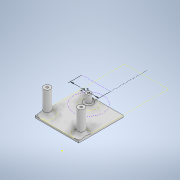
# Autodesk Inventor part: suport dintr-o bucata
Saved by Autodesk Inventor 2022.6 (Build 266554000, 554)
## iProperties
Created: 2026-10-28
Part Number: suport dintr-o bucata
Material: Generic
Document SubType Name: Modeling
Designer: Dragos Macovei
Density: 1 g/cm^3
Appearance: Default
Author: Dragos Macovei
Autodesk Inventor part; units mm, degrees
ref_plane "YZ Plane" through (0, 0, 0) normal (1, 0, 0) x (0, 1, 0)
ref_plane "XZ Plane" through (0, 0, 0) normal (0, 1, 0) x (-1, 0, 0)
ref_plane "XY Plane" through (0, 0, 0) normal (0, 0, 1) x (1, 0, 0)
sketch "Sketch1" plane through (0, 0, 0) normal (0, 1, 0) x (-1, 0, 0)
  line L0 (0, 0) -> (45, 0)
  line L1 (45, 0) -> (45, -109.7465)
  line L2 (45, -109.7465) -> (0, -109.7465)
  line L3 (0, -109.7465) -> (0, 0)
  dimension "d35" = 45
  constraints: 8 end point, 2 parallel, 1 horizontal, 1 perpendicular
  measures "d35" distance between parallel lines of L3 L1
extrude "Extrusion1" add sketch "Sketch1" along normal blind 2
sketch "Sketch2" plane through (0, 2, 0) normal (0, 1, 0) x (1, 0, 0)
  circle A0 centre (-40, 24.934) radius 3.5
  circle A1 centre (-5, 24.934) radius 3.5
  circle A2 centre (-5, 24.934) radius 1.15
  circle A3 centre (-40, 24.934) radius 1.15
  line L0 (0, 0) -> (0, 109.7465) projected
  dimension "d2" = 35
  dimension "d3" = 7
  dimension "d4" = 7
  dimension "d5" = 2.3
  dimension "d6" = 2.3
  dimension "d7" = 5
  constraints: 4 centre point, 2 coincident
  measures "d2" distance of A0.centre A1.centre
  measures "d3" diameter of A1
  measures "d4" diameter of A0
  measures "d5" diameter of A2
  measures "d6" diameter of A3
  measures "d7" distance from line of L0 A1.centre
extrude "Extrusion2" add sketch "Sketch2" along normal blind 24
sketch "Sketch3" plane through (0, 2, 0) normal (0, 1, 0) x (1, 0, 0)
  circle A0 centre (-40, 24.934) radius 1.15 projected
  circle A1 centre (-5, 24.934) radius 1.15 projected
  line L0 (-50.8787, 24.934) -> (5.8787, 24.934) construction
  line L1 (-22.5, 24.934) -> (-22.5, 31.434) construction
  circle A2 centre (-22.5, 31.434) radius 2.5 construction
  circle A3 centre (-22.5, 31.434) radius 4.5415 construction
  circle A4 centre (-27.7085, 55.203) radius 2.65
  circle A5 centre (-27.7085, 55.203) radius 1.15
  line L2 (-22.5, 24.934) -> (-22.5, 95.6611)
  circle A6 centre (-27.7085, 55.203) radius 20.2915 construction
  line L3 (-22.5, 55.203) -> (-52, 55.203)
  circle A7 centre (-52, 55.203) radius 4.5
  point P0 (0, 0)
  dimension "d10" = 6.5
  dimension "d11" = 5
  dimension "d12" = 9.083
  dimension "d15" = 5.3
  dimension "d16" = 2.3
  dimension "d31" = 17.5
  dimension "d39" = 40.583
  dimension "d40" = 29.5
  dimension "d41" = 9
  dimension "d42" = 0.5
  dimension "d43" = 0.5
  constraints: 8 end point, 6 centre point, 5 coincident, 3 point on line, 2 horizontal, 2 vertical, 1 midpoint
  measures "d10" distance of L1.start L1.end
  measures "d11" diameter of A2
  measures "d12" diameter of A3
  measures "d15" diameter of A4
  measures "d16" diameter of A5
  measures "d31" distance from line of A1.centre L1
  measures "d39" diameter of A6
  measures "d40" distance of L3.start L3.end
  measures "d41" diameter of A7
extrude "Extrusion3" add sketch "Sketch3" along normal blind 10 contours L3 A5 A4 | A4 L3 A5
sketch "Sketch4" plane through (0, 2, 0) normal (0, 1, 0) x (1, 0, 0)
  line L0 (0, 109.7465) -> (-45, 109.7465) projected
  line L1 (-45, 109.7465) -> (-45, 0) projected
  line L2 (-45, 0) -> (0, 0) projected
  line L3 (0, 0) -> (0, 109.7465) projected
  circle A0 centre (-40, 24.934) radius 3.5 projected
  circle A1 centre (-5, 24.934) radius 3.5 projected
  circle A2 centre (-27.7085, 55.203) radius 2.65 projected
  circle A3 centre (-27.7085, 55.203) radius 4.65
  circle A4 centre (-40, 24.934) radius 1.15 projected
  dimension "d19" = 9.3
  constraints: 1 centre point, 1 coincident
  measures "d19" diameter of A3
extrude "Extrusion4" add sketch "Sketch4" along normal blind 2 contours A3
fillet "Fillet1" radius 4 2 edges at (-43.5, 2, -24.934) (-8.5, 2, -24.934)
fillet "Fillet2" radius 4 1 edges at (-32.3585, 2, -55.203)
fillet "Fillet3" radius 1 1 edges at (-28.8585, 2, -55.203)
fillet "Fillet4" radius 1 2 edges at (-6.15, 2, -24.934) (-41.15, 2, -24.934)
sketch "Sketch6" plane through (0, 2, 0) normal (0, 1, 0) x (1, 0, 0)
  line L0 (-45, 0) -> (0, 0)
  line L1 (0, 0) -> (0, 17.434)
  line L2 (0, 17.434) -> (-45, 17.434)
  line L3 (-45, 17.434) -> (-45, 0)
  arc A0 (-45, 19.3438) -> (-45, 30.5242) centre (-40, 24.934) ccw projected
  point P0 (0, 0)
  constraints: 8 end point, 2 parallel, 1 horizontal, 1 perpendicular, 1 tangent
extrude "Extrusion6" cut sketch "Sketch6" against normal blind 10
sketch "Sketch7" plane through (0, 2, 0) normal (0, 1, 0) x (1, 0, 0)
  circle A0 centre (-27.7085, 55.203) radius 1.15 construction
  line L0 (-40, 17.434) -> (-5, 17.434) construction
  arc A1 (0, 30.5242) -> (-5, 17.434) centre (-5, 24.934) ccw construction
  line L1 (0, 30.5242) -> (0, 109.7465) construction
  line L2 (0, 109.7465) -> (-45, 109.7465) construction
  line L3 (-45, 109.7465) -> (-45, 30.5242) construction
  arc A2 (-40, 17.434) -> (-45, 30.5242) centre (-40, 24.934) ccw construction
  circle A3 centre (-27.7085, 55.203) radius 8.1141 construction
  circle A4 centre (-27.7085, 55.203) radius 2.65 construction
  line L4 (-27.7085, 55.203) -> (-27.7085, 115.2563) construction
  line L5 (-27.7085, 77.9114) -> (-57.2085, 77.9114) construction
  circle A5 centre (-27.7085, 55.203) radius 0.15 construction
  circle A6 centre (-27.7085, 55.203) radius 15.1981 construction
  point P0 (0, 0)
  dimension "d38" = 29.5
  constraints: 4 end point, 1 centre point, 1 coincident, 1 horizontal, 1 point on line, 1 vertical
  measures "d38" distance of L5.start L5.end
sketch "Sketch8" plane through (0, 2, 0) normal (0, 1, 0) x (1, 0, 0)
  line L0 (0, 30.5242) -> (0, 109.7465) projected
  line L1 (-45, 109.7465) -> (-45, 30.5242) projected
  line L2 (0, 109.7465) -> (-45, 109.7465)
  line L3 (-45, 109.7465) -> (-45, 63.1835)
  line L4 (-45, 63.1835) -> (0, 63.1835)
  line L5 (0, 63.1835) -> (0, 109.7465)
  point P0 (0, 0)
  constraints: 8 end point, 2 parallel, 1 horizontal, 1 perpendicular, 1 point on line
extrude "Extrusion7" cut sketch "Sketch8" against normal blind 10
body "Solid1"
